211102_P01_WALL-PANEL-FRAME-SIDE-LOWER-RH_CAD (Autodesk Fusion 360 design; units mm, degrees)
description: WALL - PANEL FRAME - SIDE LOWER - RH | Vách phải - khung dưới | P01 | position R1
part number: 211102
description: WALL - PANEL FRAME - SIDE LOWER - RH | Vách phải - khung dưới | P01
Autodesk Fusion 360 part; units mm, degrees
ref_plane "WorkPlane1" through (0, 0, 112.26) normal (0, 0, 1) x (1, 0, 0) in component "211102 WALL - PANEL FRAME - SIDE LOWER - RH"
sketch "SKETCH - RAIL - BOTTOM TUBE" plane through (0, 0, 112.26) normal (0, 0, 1) x (1, 0, 0) in component "211102 WALL - PANEL FRAME - SIDE LOWER - RH"
  line L0 (1204, -642.74) -> (1244, -642.74)
  line L1 (1244, -642.74) -> (1244, 847)
  line L2 (1244, 847) -> (1204, 847)
  line L3 (1204, 847) -> (1204, -642.74)
  dimension "d494" = 40
  dimension "d495" = 1489.74
  dimension "d496" = 1204
  dimension "d497" = 642.74
  constraint horizontal L0
  constraint vertical L1
  constraint horizontal L2
  constraint vertical L3
  measures "d494" horizontal distance of L0.start L0.end
  measures "d495" vertical distance of L0.start L2.end
  measures "d496" horizontal distance of origin L0.start
  measures "d497" vertical distance of origin L0.start
extrude "EXTRUDE - RAIL - BOTTOM TUBE" add sketch "SKETCH - RAIL - BOTTOM TUBE" along normal blind 20 makes body 1 in component "211102 WALL - PANEL FRAME - SIDE LOWER - RH"
ref_plane "WorkPlane2" through (0, 0, 113.46) normal (0, 0, 1) x (1, 0, 0) in component "211102 WALL - PANEL FRAME - SIDE LOWER - RH"
sketch "SKETCH - RAIL - BOTTOM BORE" plane through (0, 0, 113.46) normal (0, 0, 1) x (1, 0, 0) in component "211102 WALL - PANEL FRAME - SIDE LOWER - RH"
  line L0 (1205.2, -642.74) -> (1242.8, -642.74)
  line L1 (1242.8, -642.74) -> (1242.8, 847)
  line L2 (1242.8, 847) -> (1205.2, 847)
  line L3 (1205.2, 847) -> (1205.2, -642.74)
  dimension "d502" = 37.6
  dimension "d503" = 1489.74
  dimension "d504" = 1205.2
  dimension "d505" = 642.74
  constraint horizontal L0
  constraint vertical L1
  constraint horizontal L2
  constraint vertical L3
  measures "d502" horizontal distance of L0.start L0.end
  measures "d503" vertical distance of L0.start L2.end
  measures "d504" horizontal distance of origin L0.start
  measures "d505" vertical distance of origin L0.start
extrude "CUT - RAIL - BOTTOM BORE" cut sketch "SKETCH - RAIL - BOTTOM BORE" along normal blind 17.6 bodies 1 in component "211102 WALL - PANEL FRAME - SIDE LOWER - RH"
ref_plane "WorkPlane3" through (0, 0, 1235) normal (0, 0, 1) x (1, 0, 0) in component "211102 WALL - PANEL FRAME - SIDE LOWER - RH"
sketch "SKETCH - RAIL - TOP TUBE" plane through (0, 0, 1235) normal (0, 0, 1) x (1, 0, 0) in component "211102 WALL - PANEL FRAME - SIDE LOWER - RH"
  line L0 (1204, -642.74) -> (1244, -642.74)
  line L1 (1244, -642.74) -> (1244, 847)
  line L2 (1244, 847) -> (1204, 847)
  line L3 (1204, 847) -> (1204, -642.74)
  dimension "d510" = 40
  dimension "d511" = 1489.74
  dimension "d512" = 1204
  dimension "d513" = 642.74
  constraint horizontal L0
  constraint vertical L1
  constraint horizontal L2
  constraint vertical L3
  measures "d510" horizontal distance of L0.start L0.end
  measures "d511" vertical distance of L0.start L2.end
  measures "d512" horizontal distance of origin L0.start
  measures "d513" vertical distance of origin L0.start
extrude "EXTRUDE - RAIL - TOP TUBE" add sketch "SKETCH - RAIL - TOP TUBE" along normal blind 20 separate body makes body 2 in component "211102 WALL - PANEL FRAME - SIDE LOWER - RH"
ref_plane "WorkPlane4" through (0, 0, 1236.2) normal (0, 0, 1) x (1, 0, 0) in component "211102 WALL - PANEL FRAME - SIDE LOWER - RH"
sketch "SKETCH - RAIL - TOP BORE" plane through (0, 0, 1236.2) normal (0, 0, 1) x (1, 0, 0) in component "211102 WALL - PANEL FRAME - SIDE LOWER - RH"
  line L0 (1205.2, -642.74) -> (1242.8, -642.74)
  line L1 (1242.8, -642.74) -> (1242.8, 847)
  line L2 (1242.8, 847) -> (1205.2, 847)
  line L3 (1205.2, 847) -> (1205.2, -642.74)
  dimension "d518" = 37.6
  dimension "d519" = 1489.74
  dimension "d520" = 1205.2
  dimension "d521" = 642.74
  constraint horizontal L0
  constraint vertical L1
  constraint horizontal L2
  constraint vertical L3
  measures "d518" horizontal distance of L0.start L0.end
  measures "d519" vertical distance of L0.start L2.end
  measures "d520" horizontal distance of origin L0.start
  measures "d521" vertical distance of origin L0.start
extrude "CUT - RAIL - TOP BORE" cut sketch "SKETCH - RAIL - TOP BORE" along normal blind 17.6 bodies 2 in component "211102 WALL - PANEL FRAME - SIDE LOWER - RH"
ref_plane "WorkPlane5" through (0, 0, 132.26) normal (0, 0, 1) x (1, 0, 0) in component "211102 WALL - PANEL FRAME - SIDE LOWER - RH"
sketch "SKETCH - STILE - FRONT TUBE" plane through (0, 0, 132.26) normal (0, 0, 1) x (1, 0, 0) in component "211102 WALL - PANEL FRAME - SIDE LOWER - RH"
  line L0 (1204, -642.74) -> (1244, -642.74)
  line L1 (1244, -642.74) -> (1244, -622.74)
  line L2 (1244, -622.74) -> (1204, -622.74)
  line L3 (1204, -622.74) -> (1204, -642.74)
  dimension "d526" = 40
  dimension "d527" = 20
  dimension "d528" = 1204
  dimension "d529" = 642.74
  constraint horizontal L0
  constraint vertical L1
  constraint horizontal L2
  constraint vertical L3
  measures "d526" horizontal distance of L0.start L0.end
  measures "d527" vertical distance of L0.start L2.end
  measures "d528" horizontal distance of origin L0.start
  measures "d529" vertical distance of origin L0.start
extrude "EXTRUDE - STILE - FRONT TUBE" add sketch "SKETCH - STILE - FRONT TUBE" along normal blind 1102.74 separate body makes body 3 in component "211102 WALL - PANEL FRAME - SIDE LOWER - RH"
ref_plane "WorkPlane6" through (0, 0, 132.26) normal (0, 0, 1) x (1, 0, 0) in component "211102 WALL - PANEL FRAME - SIDE LOWER - RH"
sketch "SKETCH - STILE - FRONT BORE" plane through (0, 0, 132.26) normal (0, 0, 1) x (1, 0, 0) in component "211102 WALL - PANEL FRAME - SIDE LOWER - RH"
  line L0 (1205.2, -641.54) -> (1242.8, -641.54)
  line L1 (1242.8, -641.54) -> (1242.8, -623.94)
  line L2 (1242.8, -623.94) -> (1205.2, -623.94)
  line L3 (1205.2, -623.94) -> (1205.2, -641.54)
  dimension "d534" = 37.6
  dimension "d535" = 17.6
  dimension "d536" = 1205.2
  dimension "d537" = 641.54
  constraint horizontal L0
  constraint vertical L1
  constraint horizontal L2
  constraint vertical L3
  measures "d534" horizontal distance of L0.start L0.end
  measures "d535" vertical distance of L0.start L2.end
  measures "d536" horizontal distance of origin L0.start
  measures "d537" vertical distance of origin L0.start
extrude "CUT - STILE - FRONT BORE" cut sketch "SKETCH - STILE - FRONT BORE" along normal blind 1102.74 bodies 3 in component "211102 WALL - PANEL FRAME - SIDE LOWER - RH"
ref_plane "WorkPlane7" through (0, 0, 132.26) normal (0, 0, 1) x (1, 0, 0) in component "211102 WALL - PANEL FRAME - SIDE LOWER - RH"
sketch "SKETCH - STILE - BACK TUBE" plane through (0, 0, 132.26) normal (0, 0, 1) x (1, 0, 0) in component "211102 WALL - PANEL FRAME - SIDE LOWER - RH"
  line L0 (1204, 807) -> (1244, 807)
  line L1 (1244, 807) -> (1244, 847)
  line L2 (1244, 847) -> (1204, 847)
  line L3 (1204, 847) -> (1204, 807)
  dimension "d542" = 40
  dimension "d543" = 40
  dimension "d544" = 1204
  dimension "d545" = 807
  constraint horizontal L0
  constraint vertical L1
  constraint horizontal L2
  constraint vertical L3
  measures "d542" horizontal distance of L0.start L0.end
  measures "d543" vertical distance of L0.start L2.end
  measures "d544" horizontal distance of origin L0.start
  measures "d545" vertical distance of origin L0.start
extrude "EXTRUDE - STILE - BACK TUBE" add sketch "SKETCH - STILE - BACK TUBE" along normal blind 1102.74 separate body makes body 4 in component "211102 WALL - PANEL FRAME - SIDE LOWER - RH"
ref_plane "WorkPlane8" through (0, 0, 132.26) normal (0, 0, 1) x (1, 0, 0) in component "211102 WALL - PANEL FRAME - SIDE LOWER - RH"
sketch "SKETCH - STILE - BACK BORE" plane through (0, 0, 132.26) normal (0, 0, 1) x (1, 0, 0) in component "211102 WALL - PANEL FRAME - SIDE LOWER - RH"
  line L0 (1205.2, 808.2) -> (1242.8, 808.2)
  line L1 (1242.8, 808.2) -> (1242.8, 845.8)
  line L2 (1242.8, 845.8) -> (1205.2, 845.8)
  line L3 (1205.2, 845.8) -> (1205.2, 808.2)
  dimension "d550" = 37.6
  dimension "d551" = 37.6
  dimension "d552" = 1205.2
  dimension "d553" = 808.2
  constraint horizontal L0
  constraint vertical L1
  constraint horizontal L2
  constraint vertical L3
  measures "d550" horizontal distance of L0.start L0.end
  measures "d551" vertical distance of L0.start L2.end
  measures "d552" horizontal distance of origin L0.start
  measures "d553" vertical distance of origin L0.start
extrude "CUT - STILE - BACK BORE" cut sketch "SKETCH - STILE - BACK BORE" along normal blind 1102.74 bodies 4 in component "211102 WALL - PANEL FRAME - SIDE LOWER - RH"
ref_plane "WorkPlane9" through (0, 0, 132.26) normal (0, 0, 1) x (1, 0, 0) in component "211102 WALL - PANEL FRAME - SIDE LOWER - RH"
sketch "SKETCH - STILE - MID 1 TUBE" plane through (0, 0, 132.26) normal (0, 0, 1) x (1, 0, 0) in component "211102 WALL - PANEL FRAME - SIDE LOWER - RH"
  line L0 (1204, -277.805) -> (1244, -277.805)
  line L1 (1244, -277.805) -> (1244, -257.805)
  line L2 (1244, -257.805) -> (1204, -257.805)
  line L3 (1204, -257.805) -> (1204, -277.805)
  dimension "d558" = 40
  dimension "d559" = 20
  dimension "d560" = 1204
  dimension "d561" = 277.805
  constraint horizontal L0
  constraint vertical L1
  constraint horizontal L2
  constraint vertical L3
  measures "d558" horizontal distance of L0.start L0.end
  measures "d559" vertical distance of L0.start L2.end
  measures "d560" horizontal distance of origin L0.start
  measures "d561" vertical distance of origin L0.start
extrude "EXTRUDE - STILE - MID 1 TUBE" add sketch "SKETCH - STILE - MID 1 TUBE" along normal blind 1102.74 separate body makes body 5 in component "211102 WALL - PANEL FRAME - SIDE LOWER - RH"
ref_plane "WorkPlane10" through (0, 0, 132.26) normal (0, 0, 1) x (1, 0, 0) in component "211102 WALL - PANEL FRAME - SIDE LOWER - RH"
sketch "SKETCH - STILE - MID 1 BORE" plane through (0, 0, 132.26) normal (0, 0, 1) x (1, 0, 0) in component "211102 WALL - PANEL FRAME - SIDE LOWER - RH"
  line L0 (1205, -276.805) -> (1243, -276.805)
  line L1 (1243, -276.805) -> (1243, -258.805)
  line L2 (1243, -258.805) -> (1205, -258.805)
  line L3 (1205, -258.805) -> (1205, -276.805)
  dimension "d566" = 38
  dimension "d567" = 18
  dimension "d568" = 1205
  dimension "d569" = 276.805
  constraint horizontal L0
  constraint vertical L1
  constraint horizontal L2
  constraint vertical L3
  measures "d566" horizontal distance of L0.start L0.end
  measures "d567" vertical distance of L0.start L2.end
  measures "d568" horizontal distance of origin L0.start
  measures "d569" vertical distance of origin L0.start
extrude "CUT - STILE - MID 1 BORE" cut sketch "SKETCH - STILE - MID 1 BORE" along normal blind 1102.74 bodies 5 in component "211102 WALL - PANEL FRAME - SIDE LOWER - RH"
pattern_linear "PATTERN - STILES - MID" count 3 spacing 364.935 along (0, 1, 0) of bodies 5 makes body 6 at (1230.6667, 107.13, 499.84) makes body 7 at (1230.6667, 472.065, 499.84) in component "211102 WALL - PANEL FRAME - SIDE LOWER - RH"
ref_plane "WorkPlane11" through (0, 0, 112.26) normal (0, 0, 1) x (1, 0, 0) in component "211102 WALL - PANEL FRAME - SIDE LOWER - RH"
sketch "HOLE CENTRE - BOTTOM RAIL BOLT CLEARANCE 1" plane through (0, 0, 112.26) normal (0, 0, 1) x (1, 0, 0) in component "211102 WALL - PANEL FRAME - SIDE LOWER - RH"
  point P0 (1224, -422.74)
  dimension "d578" = 1224
  dimension "d579" = 422.74
  measures "d578" horizontal distance of origin P0
  measures "d579" vertical distance of origin P0
hole "HOLE - BOTTOM RAIL BOLT CLEARANCE 1" at (1224, -422.74, 112.26) direction (0, 0, 1) diameter 7 depth 1.2 tip angle 118 bodies 1 in component "211102 WALL - PANEL FRAME - SIDE LOWER - RH"
ref_plane "WorkPlane12" through (0, 0, 132.26) normal (0, 0, 1) x (1, 0, 0) in component "211102 WALL - PANEL FRAME - SIDE LOWER - RH"
sketch "HOLE CENTRE - BOTTOM RAIL KEY ACCESS 1" plane through (0, 0, 132.26) normal (0, 0, 1) x (1, 0, 0) in component "211102 WALL - PANEL FRAME - SIDE LOWER - RH"
  point P0 (1224, -422.74)
  dimension "d585" = 1224
  dimension "d586" = 422.74
  measures "d585" horizontal distance of origin P0
  measures "d586" vertical distance of origin P0
hole "HOLE - BOTTOM RAIL KEY ACCESS 1" at (1224, -422.74, 132.26) direction (0, 0, -1) diameter 19 depth 1.2 tip angle 118 bodies 1 in component "211102 WALL - PANEL FRAME - SIDE LOWER - RH"
pattern_linear "PATTERN - BOTTOM RAIL BOLT HOLES" count 4 spacing 350.9133 along (0, 1, 0) of "HOLE - BOTTOM RAIL BOLT CLEARANCE 1", "HOLE - BOTTOM RAIL KEY ACCESS 1" in component "211102 WALL - PANEL FRAME - SIDE LOWER - RH"
ref_plane "WorkPlane13" through (0, 0, 112.26) normal (0, 0, 1) x (1, 0, 0) in component "211102 WALL - PANEL FRAME - SIDE LOWER - RH"
sketch "HOLE CENTRE - BOTTOM RAIL SPIGOT ROUND" plane through (0, 0, 112.26) normal (0, 0, 1) x (1, 0, 0) in component "211102 WALL - PANEL FRAME - SIDE LOWER - RH"
  point P0 (1224, -542.74)
  dimension "d596" = 1224
  dimension "d597" = 542.74
  measures "d596" horizontal distance of origin P0
  measures "d597" vertical distance of origin P0
hole "HOLE - BOTTOM RAIL SPIGOT ROUND" at (1224, -542.74, 112.26) direction (0, 0, 1) diameter 8.5 depth 1.2 tip angle 118 bodies 1 in component "211102 WALL - PANEL FRAME - SIDE LOWER - RH"
ref_plane "WorkPlane14" through (0, 0, 112.26) normal (0, 0, 1) x (1, 0, 0) in component "211102 WALL - PANEL FRAME - SIDE LOWER - RH"
sketch "SKETCH - BOTTOM RAIL SPIGOT SLOT" plane through (0, 0, 112.26) normal (0, 0, 1) x (1, 0, 0) in component "211102 WALL - PANEL FRAME - SIDE LOWER - RH"
  line L0 (1221.25, 745.75) -> (1226.75, 745.75)
  line L1 (1226.75, 745.75) -> (1226.75, 754.25)
  line L2 (1226.75, 754.25) -> (1221.25, 754.25)
  line L3 (1221.25, 754.25) -> (1221.25, 745.75)
  dimension "d603" = 5.5
  dimension "d604" = 8.5
  dimension "d605" = 1221.25
  dimension "d606" = 745.75
  constraint horizontal L0
  constraint vertical L1
  constraint horizontal L2
  constraint vertical L3
  measures "d603" horizontal distance of L0.start L0.end
  measures "d604" vertical distance of L0.start L2.end
  measures "d605" horizontal distance of origin L0.start
  measures "d606" vertical distance of origin L0.start
extrude "CUT - BOTTOM RAIL SPIGOT SLOT" cut sketch "SKETCH - BOTTOM RAIL SPIGOT SLOT" along normal blind 1.2 bodies 1 in component "211102 WALL - PANEL FRAME - SIDE LOWER - RH"
ref_plane "WorkPlane15" through (0, 0, 112.26) normal (0, 0, 1) x (1, 0, 0) in component "211102 WALL - PANEL FRAME - SIDE LOWER - RH"
sketch "HOLE CENTRE - BOTTOM RAIL SPIGOT SLOT END 1" plane through (0, 0, 112.26) normal (0, 0, 1) x (1, 0, 0) in component "211102 WALL - PANEL FRAME - SIDE LOWER - RH"
  point P0 (1221.25, 750)
  dimension "d611" = 1221.25
  dimension "d612" = 750
  measures "d611" horizontal distance of origin P0
  measures "d612" vertical distance of origin P0
hole "HOLE - BOTTOM RAIL SPIGOT SLOT END 1" at (1221.25, 750, 112.26) direction (0, 0, 1) diameter 8.5 depth 1.2 tip angle 118 bodies 1 in component "211102 WALL - PANEL FRAME - SIDE LOWER - RH"
ref_plane "WorkPlane16" through (0, 0, 112.26) normal (0, 0, 1) x (1, 0, 0) in component "211102 WALL - PANEL FRAME - SIDE LOWER - RH"
sketch "HOLE CENTRE - BOTTOM RAIL SPIGOT SLOT END 2" plane through (0, 0, 112.26) normal (0, 0, 1) x (1, 0, 0) in component "211102 WALL - PANEL FRAME - SIDE LOWER - RH"
  point P0 (1226.75, 750)
  dimension "d618" = 1226.75
  dimension "d619" = 750
  measures "d618" horizontal distance of origin P0
  measures "d619" vertical distance of origin P0
hole "HOLE - BOTTOM RAIL SPIGOT SLOT END 2" at (1226.75, 750, 112.26) direction (0, 0, 1) diameter 8.5 depth 1.2 tip angle 118 bodies 1 in component "211102 WALL - PANEL FRAME - SIDE LOWER - RH"
ref_plane "WorkPlane17" through (0, 0, 1255) normal (0, 0, 1) x (1, 0, 0) in component "211102 WALL - PANEL FRAME - SIDE LOWER - RH"
sketch "HOLE CENTRE - TOP RAIL RIVNUT 1" plane through (0, 0, 1255) normal (0, 0, 1) x (1, 0, 0) in component "211102 WALL - PANEL FRAME - SIDE LOWER - RH"
  point P0 (1224, -422.74)
  dimension "d625" = 1224
  dimension "d626" = 422.74
  measures "d625" horizontal distance of origin P0
  measures "d626" vertical distance of origin P0
hole "HOLE - TOP RAIL RIVNUT 1" at (1224, -422.74, 1255) direction (0, 0, -1) diameter 9.53 depth 1.2 tip angle 118 bodies 2 in component "211102 WALL - PANEL FRAME - SIDE LOWER - RH"
pattern_linear "PATTERN - TOP RAIL RIVNUTS" count 4 spacing 350.9133 along (0, 1, 0) of "HOLE - TOP RAIL RIVNUT 1" in component "211102 WALL - PANEL FRAME - SIDE LOWER - RH"
ref_plane "WorkPlane18" through (0, 0, 1255) normal (0, 0, 1) x (1, 0, 0) in component "211102 WALL - PANEL FRAME - SIDE LOWER - RH"
sketch "HOLE CENTRE - TOP RAIL SPIGOT RIVNUT FRONT" plane through (0, 0, 1255) normal (0, 0, 1) x (1, 0, 0) in component "211102 WALL - PANEL FRAME - SIDE LOWER - RH"
  point P0 (1224, -542.74)
  dimension "d636" = 1224
  dimension "d637" = 542.74
  measures "d636" horizontal distance of origin P0
  measures "d637" vertical distance of origin P0
hole "HOLE - TOP RAIL SPIGOT RIVNUT FRONT" at (1224, -542.74, 1255) direction (0, 0, -1) diameter 9.53 depth 1.2 tip angle 118 bodies 2 in component "211102 WALL - PANEL FRAME - SIDE LOWER - RH"
ref_plane "WorkPlane19" through (0, 0, 1255) normal (0, 0, 1) x (1, 0, 0) in component "211102 WALL - PANEL FRAME - SIDE LOWER - RH"
sketch "HOLE CENTRE - TOP RAIL SPIGOT RIVNUT BACK" plane through (0, 0, 1255) normal (0, 0, 1) x (1, 0, 0) in component "211102 WALL - PANEL FRAME - SIDE LOWER - RH"
  point P0 (1224, 750)
  dimension "d643" = 1224
  dimension "d644" = 750
  measures "d643" horizontal distance of origin P0
  measures "d644" vertical distance of origin P0
hole "HOLE - TOP RAIL SPIGOT RIVNUT BACK" at (1224, 750, 1255) direction (0, 0, -1) diameter 9.53 depth 1.2 tip angle 118 bodies 2 in component "211102 WALL - PANEL FRAME - SIDE LOWER - RH"
ref_plane "WorkPlane20" through (0, -642.74, 0) normal (0, 1, 0) x (0, 0, 1) in component "211102 WALL - PANEL FRAME - SIDE LOWER - RH"
sketch "HOLE CENTRE - FRONT STILE BOLT CLEARANCE 1" plane through (0, -642.74, 0) normal (0, 1, 0) x (1, 0, 0) in component "211102 WALL - PANEL FRAME - SIDE LOWER - RH"
  point P0 (1224, -332.26)
  dimension "d650" = 1224
  dimension "d651" = 332.26
  measures "d650" horizontal distance of origin P0
  measures "d651" vertical distance of origin P0
hole "HOLE - FRONT STILE BOLT CLEARANCE 1" at (1224, -642.74, 332.26) direction (0, 1, 0) diameter 7 depth 1.2 tip angle 118 bodies 3 in component "211102 WALL - PANEL FRAME - SIDE LOWER - RH"
ref_plane "WorkPlane21" through (0, -622.74, 0) normal (0, 1, 0) x (0, 0, 1) in component "211102 WALL - PANEL FRAME - SIDE LOWER - RH"
sketch "HOLE CENTRE - FRONT STILE KEY ACCESS 1" plane through (0, -622.74, 0) normal (0, 1, 0) x (1, 0, 0) in component "211102 WALL - PANEL FRAME - SIDE LOWER - RH"
  point P0 (1224, -332.26)
  dimension "d657" = 1224
  dimension "d658" = 332.26
  measures "d657" horizontal distance of origin P0
  measures "d658" vertical distance of origin P0
hole "HOLE - FRONT STILE KEY ACCESS 1" at (1224, -622.74, 332.26) direction (0, -1, 0) diameter 19 depth 1.2 tip angle 118 bodies 3 in component "211102 WALL - PANEL FRAME - SIDE LOWER - RH"
pattern_linear "PATTERN - FRONT STILE BOLT HOLES" count 3 spacing 351.37 along (0, 0, 1) of "HOLE - FRONT STILE BOLT CLEARANCE 1", "HOLE - FRONT STILE KEY ACCESS 1" in component "211102 WALL - PANEL FRAME - SIDE LOWER - RH"
ref_plane "WorkPlane22" through (1204, 0, 0) normal (1, 0, 0) x (0, 1, 0) in component "211102 WALL - PANEL FRAME - SIDE LOWER - RH"
sketch "HOLE CENTRE - BACK STILE CORNER RIVNUT 1" plane through (1204, 0, 0) normal (1, 0, 0) x (0, 0, -1) in component "211102 WALL - PANEL FRAME - SIDE LOWER - RH"
  point P0 (-332.26, 824)
  dimension "d668" = 824
  dimension "d669" = 332.26
  measures "d668" vertical distance of origin P0
  measures "d669" horizontal distance of origin P0
hole "HOLE - BACK STILE CORNER RIVNUT 1" at (1204, 824, 332.26) direction (1, 0, 0) diameter 9.53 depth 1.2 tip angle 118 bodies 4 in component "211102 WALL - PANEL FRAME - SIDE LOWER - RH"
pattern_linear "PATTERN - BACK STILE CORNER RIVNUTS" count 3 spacing 339.305 along (0, 0, 1) of "HOLE - BACK STILE CORNER RIVNUT 1" in component "211102 WALL - PANEL FRAME - SIDE LOWER - RH"
component "211102 WALL - PANEL FRAME - SIDE LOWER - RH" placed x (1, 0, 0) y (0, 1, 0) z (0, 0, 1) at (0, 0, 0)
equation "pod_w_Ref = 2500 mm" comment "DECIDED: D-01; conventions s4 (X = +-1250)"
equation "pod_d_Ref = 1700 mm" comment "DECIDED: D-01; conventions s4 (Y = +-850)"
equation "pod_h_Ref = 2400 mm" comment "DECIDED: D-21 (room floor to roof skin top)"
equation "glide_h_Ref = 10 mm" comment "ASSUMPTION: layout study inputs.py glide_h"
equation "band_h_Ref = 100 mm" comment "SOURCE: layout study B1 list B-BAND 100x40; inputs.py base_h"
equation "outer_t_Ref = skin_t_Ref + bond_t_Ref + frame_t_Ref" comment "DECIDED: PM ruling 2026-10-31: ACP 3 + bond line 3 + frame 40, walls and ceiling (was 43)"
equation "cav_gap_Ref = 4 mm" comment "DECIDED: D-16, D-42: the gap between the outer panel and the lining cassette in the wall and ceiling stack"
equation "cass_t_Ref = 34 mm" comment "SOURCE: layout study B1 final list L-CASS 34 (tray + 25 gap + felt 9)"
equation "stack_t_Ref = outer_t_Ref + cav_gap_Ref + cass_t_Ref" comment "CALCULATION: D-16, D-42 stack, walls and ceiling: outer panel + cavity gap + cassette (PM ruling 2026-10-31 on outer_t)"
equation "wall_depth_Ref = 1495 mm" comment "DECIDED: PM ruling pass C: side walls start at the decor back plate (Y -645), as v1 (1496)"
equation "lin_gap_Ref = 4 mm" comment "ASSUMPTION: PM ruling pass C: gap above the upper side linings so they stay floating (= the 4 mm stack gap)"
equation "seam_gap_Ref = 2.26 mm" comment "DECIDED: PM ruling 2026-10-31 (Mechanical Checker F-001, F-005): the Joints Engineer's 2.26 mm at all nine site seam types, set by a metal stop (1.5 stop washer + 0.76 rivnut head; joints register section 2.8)"
equation "wall_z0_Ref = glide_h_Ref + band_h_Ref" comment "CALCULATION: base band top: glides + band"
equation "panel_z0_Ref = wall_z0_Ref + seam_gap_Ref" comment "CALCULATION: walls stand one seam_gap above the band top (joints register 2.8, IF-01)"
equation "wall_h_Ref = pod_h_Ref - wall_z0_Ref" comment "CALCULATION: 2290 = layout study v2_model wall_h"
equation "side_h_Ref = ( wall_h_Ref - 2 * seam_gap_Ref ) / 2" comment "CALCULATION: D-23: 2 sheets per side wall; the gap on the band and the horizontal seam (joints register 2.8)"
equation "back_oh_Ref = pod_h_Ref - outer_t_Ref - seam_gap_Ref - panel_z0_Ref" comment "CALCULATION: PM ruling 2026-10-31 (pass D, F-004): the back outer frames run up to the ceiling frame (pod_h - outer_t), less the seam_gap under it, closing the slot at the back top edge"
equation "back_ph_Ref = ( back_oh_Ref - seam_gap_Ref ) / 2" comment "CALCULATION: D-23: 4 sheets on the back, two equal rows with one seam_gap between them (joints register 2.8); the lower back linings match the lower row, as on the side walls"
equation "skin_t_Ref = 3 mm" comment "DECIDED: ACP skin, walls and ceiling (D-16; PM ruling 2026-10-31 on outer_t)"
equation "bond_t_Ref = 3 mm" comment "DECIDED: bond line between the ACP and the frame (PM ruling 2026-10-31 on outer_t)"
equation "frame_t_Ref = 40 mm" comment "DECIDED: aluminium frame tube depth, walls and ceiling (PM ruling 2026-10-31 on outer_t)"
equation "pod_h_Ref1 = 2400 mm" comment "DECIDED: D-21 (room floor to roof skin top)"
equation "outer_t_Ref1 = skin_t_Ref1 + bond_t_Ref1 + frame_t_Ref1" comment "DECIDED: PM ruling 2026-10-31: ACP 3 + bond line 3 + frame 40, walls and ceiling (was 43)"
equation "n_base_bolt_Ref = 4" comment "DECIDED: PM ruling 2026-10-31, J-BASE-01: bolts per panel along the band, evenly spaced"
equation "skin_t_Ref1 = 3 mm" comment "DECIDED: ACP skin, walls and ceiling (D-16; PM ruling 2026-10-31 on outer_t)"
equation "bond_t_Ref1 = 3 mm" comment "DECIDED: bond line between the ACP and the frame (PM ruling 2026-10-31 on outer_t)"
equation "frame_t_Ref1 = 40 mm" comment "DECIDED: aluminium frame tube depth, walls and ceiling (PM ruling 2026-10-31 on outer_t)"
equation "bolt_edge_inset_Ref = 220 mm" comment "DECIDED: PM ruling 2026-10-31: on every bolted edge the end bolts sit this far in from each panel end (the FRAME end, where the bolts go), the rest evenly spaced"
equation "spigot_inset_Ref = 100 mm" comment "DECIDED: PM ruling 2026-10-31: locating spigots this far in from each panel end (round hole at one end, slot at the other)"
equation "ceil_bolt_z_Ref = pod_h_Ref1 - outer_t_Ref1 + frame_t_Ref1 / 2" comment "DECIDED: PM ruling 2026-10-31, J-CEIL-01 wall to ceiling: the bolt line on the ceiling frame's centre (Z 2374)"
equation "pod_w = pod_w_Ref" comment "LINKED: pod_w_Ref, derived from 100000_P04_POD-SKELETON_CAD v4 (skeleton is the single source)"
equation "pod_d = pod_d_Ref" comment "LINKED: pod_d_Ref, derived from 100000_P04_POD-SKELETON_CAD v4 (skeleton is the single source)"
equation "pod_h = pod_h_Ref" comment "LINKED: pod_h_Ref, derived from 100000_P04_POD-SKELETON_CAD v4 (skeleton is the single source)"
equation "wall_depth = wall_depth_Ref" comment "LINKED: wall_depth_Ref, derived from 100000_P04_POD-SKELETON_CAD v4 (skeleton is the single source)"
equation "wall_z0 = wall_z0_Ref" comment "LINKED: wall_z0_Ref, derived from 100000_P04_POD-SKELETON_CAD v4 (skeleton is the single source)"
equation "panel_z0 = panel_z0_Ref" comment "LINKED: panel_z0_Ref, derived from 100000_P04_POD-SKELETON_CAD v4 (skeleton is the single source)"
equation "side_h = side_h_Ref" comment "LINKED: side_h_Ref, derived from 100000_P04_POD-SKELETON_CAD v4 (skeleton is the single source)"
equation "back_ph = back_ph_Ref" comment "LINKED: back_ph_Ref, derived from 100000_P04_POD-SKELETON_CAD v4 (skeleton is the single source)"
equation "stack_t = stack_t_Ref" comment "LINKED: stack_t_Ref, derived from 100000_P04_POD-SKELETON_CAD v4 (skeleton is the single source)"
equation "outer_t = outer_t_Ref" comment "LINKED: outer_t_Ref, derived from 100000_P04_POD-SKELETON_CAD v4 (skeleton is the single source)"
equation "cass_t = cass_t_Ref" comment "LINKED: cass_t_Ref, derived from 100000_P04_POD-SKELETON_CAD v4 (skeleton is the single source)"
equation "lin_gap = lin_gap_Ref" comment "LINKED: lin_gap_Ref, derived from 100000_P04_POD-SKELETON_CAD v4 (skeleton is the single source)"
equation "seam_gap = seam_gap_Ref" comment "LINKED: seam_gap_Ref, derived from 100000_P04_POD-SKELETON_CAD v4 (skeleton is the single source)"
equation "skin_t = skin_t_Ref" comment "LINKED: skin_t_Ref, derived from 100000_P04_POD-SKELETON_CAD v4 (skeleton is the single source)"
equation "bond_t = bond_t_Ref" comment "LINKED: bond_t_Ref, derived from 100000_P04_POD-SKELETON_CAD v4 (skeleton is the single source)"
equation "bolt_edge_inset = bolt_edge_inset_Ref" comment "LINKED: bolt_edge_inset_Ref, derived from 100000_P04_POD-SKELETON_CAD v4 (skeleton is the single source)"
equation "spigot_inset = spigot_inset_Ref" comment "LINKED: spigot_inset_Ref, derived from 100000_P04_POD-SKELETON_CAD v4 (skeleton is the single source)"
equation "n_base_bolt = n_base_bolt_Ref" comment "LINKED: n_base_bolt_Ref, derived from 100000_P04_POD-SKELETON_CAD v4 (skeleton is the single source)"
equation "ceil_bolt_z = ceil_bolt_z_Ref" comment "LINKED: ceil_bolt_z_Ref, derived from 100000_P04_POD-SKELETON_CAD v4 (skeleton is the single source)"
equation "tube_w = 20 mm" comment "CONFIRMED: D-34, D-54: aluminium tube 20 x 40 x 1.2; the 20 mm face carries the skin, so the 40 mm runs through the wall (outer_t = ACP 3 + frame 40). The joint register may turn it for the bond width (HOLD)"
equation "tube_d = outer_t - skin_t - bond_t" comment "CALCULATION: frame depth = outer panel 46 - skin 3 - bond 3 = 40 (D-34)"
equation "tube_t = 1.2 mm" comment "CONFIRMED: D-34, D-54, D-85: perimeter members (rails, front and back stiles) keep the 1.2 mm wall; they carry the rivnuts (grip check passed)"
equation "stud_t = 1.0 mm" comment "CONFIRMED: D-85 (weight): intermediate studs at a 1.0 mm wall; they carry no rivnut, only the skin's bond line"
equation "stile_pitch_max = 400 mm" comment "CONFIRMED: D-16, D-34: members 400 mm apart or less, to keep the ACP flat"
equation "pnl_len = wall_depth - seam_gap" comment "CALCULATION: D-49 depth 1495 less the 2.26 gap at the decor back plate (PM ruling on F-008): 1492.74"
equation "pnl_h = side_h" comment "CALCULATION: skeleton side_h: 2 sheets per side wall (D-23) with the seam gaps"
equation "skin_ret = outer_t - skin_t" comment "ASSUMPTION: back return of the side skin: covers the frame's back end at the corner, where the side skin covers the back panel's edge (D-55; sample drawing D04). V-groove and fold per the ACP maker (HOLD H16)"
equation "skin_setback = 0 mm" comment "ASSUMPTION: skin edge set back from the frame's top and bottom edges: 0, so the outside reveal equals the 2.26 seam gap (D-23: crisp, aligned reveals; joints register 2.8 leaves the setback to the WALL drawing)"
equation "frm_len = pnl_len - skin_t" comment "CALCULATION: the frame stops at the inside of the skin's back return"
equation "frm_h = pnl_h" comment "ASSUMPTION: the frame fills the skeleton envelope height; seam and base gasket gaps are set by the joint register (HOLD)"
equation "corner_w = 40 mm" comment "CONFIRMED: the side panel's back member is 40 x 40 x 1.2 (PM ruling on the joints register, item 3, 2026-10-31; register F2, FR-06): the back corner joint needs a 37+ mm overlap for the rivnut and the bolt"
equation "stile_n_mid = ceil(( frm_len - tube_w / 2 - corner_w / 2 ) / stile_pitch_max) - 1" comment "CALCULATION: intermediate stiles so that no stile pitch (centre to centre) exceeds stile_pitch_max"
equation "stile_pitch = ( frm_len - tube_w / 2 - corner_w / 2 ) / ( stile_n_mid + 1 )" comment "CALCULATION: equal stile pitch, centre to centre, from the front stile to the 40 mm back stile"
equation "top_h = tube_w" comment "CALCULATION: top member height: 20 on a lower panel; 40 x 40 on an upper panel, where the ceiling bolts in (PM ruling R-J3, joints register FR-06)"
equation "stile_len = frm_h - tube_w - top_h" comment "CALCULATION: stiles fit between the full-length rails (butt joints)"
equation "ceil_bolt_dz = pod_h - ceil_bolt_z" comment "CALCULATION: J-CEIL-01 side bolts on the ceiling frame tube's centre: the skeleton's ceil_bolt_z, Z 2374 on P04 (joints register R-J15, FR-07)"
equation "fill_t = tube_d" comment "CALCULATION: 40 mm PET fill fills the frame depth (D-34; layout study 40 mm)"
equation "bolt_d = 7 mm" comment "CONFIRMED: PM ruling on F-009: bolt holes 7.0 (0.51 float), position tolerance 0.4 (+-0.2) from the spigot hole, CNC or drill jig (joints register FR-02)"
equation "access_d = 19 mm" comment "CALCULATION: register FR-03: passes the 18 mm head washer (ISO 7093-1, R-J10), the M6 head and the 5 mm key; holds the grommet retainer (H-02)"
equation "bolt_line_y = pod_d / 2 - skin_t - bond_t - tube_d / 2" comment "CONFIRMED: J-WALL-02 bolt line on the back panel's tube centre, Y 824 (joints register R-J15, FR-07)"
equation "rivnut_d = 9.53 mm" comment "SOURCE: Sherex CAH3-610-4.2 hole 9.53 +0.10 (HW-SEL A5; register H-03)"
equation "spigot_d = 8.5 mm" comment "ASSUMPTION: register FR-05: hole for the 8 mm locating spigot H-05"
equation "spigot_slot = 14 mm" comment "ASSUMPTION: register FR-05: slot length for the second spigot"
equation "spigot_edge = spigot_inset" comment "CALCULATION: the skeleton's spigot_inset: spigots 100 from each end of the edge (PM ruling 2026-10-31, R-J13)"
equation "bolt_edge = bolt_edge_inset" comment "CALCULATION: the skeleton's bolt_edge_inset: end bolts 220 in from the panel's ends, evenly spaced, every bolt 30 or more from any stile (PM ruling 2026-10-31, R-J14)"
equation "n_side_jnt = 3" comment "SOURCE: register J-WALL-02, J-FRONT-01: 3 bolts up each side panel"
equation "side_jnt_pitch = ( pnl_h - 2 * bolt_edge ) / ( n_side_jnt - 1 )" comment "CALCULATION: equal pitch of the 3 bolts up the corner and decor joints"
equation "pocket_w = 60 mm" comment "ASSUMPTION: register FR-10: fill left out 60 x 60 next to each bolt for the key"
equation "corner_z0 = panel_z0" comment "CALCULATION: bottom of the back panel row this side panel meets at the corner (B1/B2 or B3/B4, skeleton P04)"
equation "corner_bolt_pitch = ( back_ph - 2 * bolt_edge ) / ( n_side_jnt - 1 )" comment "CALCULATION: J-WALL-02 bolts run along the back panel's edge: 220, 559.31, 898.61 on its 1118.61 (joints register 2.9)"
equation "n_len_bolt = n_base_bolt" comment "CALCULATION: the skeleton's n_base_bolt (4): the same count on J-WALL-01 and the J-CEIL-01 side edges (register 2.9)"
equation "ceil_bolt_pitch = ( wall_depth - 2 * bolt_edge ) / ( n_len_bolt - 1 )" comment "CALCULATION: J-CEIL-01 side edge: 4 bolts along the ceiling's 1495 from Y -645 (its front edge), 220 rule, pitch 351.67 on P04; CEILING drills the same (PM ruling 2026-10-31 16:55; joints register 2.9)"
equation "len_bolt_pitch = ( pnl_len - 2 * bolt_edge ) / ( n_len_bolt - 1 )" comment "CALCULATION: even pitch of the bolts along the panel"
equation "felt_t = 9 mm" comment "SOURCE: plan VT03-PET 9 mm PET felt; HW-SEL A3; D-31 (the factory's felt)"
equation "tray_t = 0.5 mm" comment "CONFIRMED: D-37: galvanised steel tray 0.5 mm"
equation "tray_h = cass_t" comment "CONFIRMED: PM ruling 2026-10-31 (WALL group, option 1): the wall cassettes use the ceiling's tray, returns the full cassette depth (34) turned in as lips that hold the felt, no ribs; settles H09 for the walls"
equation "lip_w = 12 mm" comment "CONFIRMED: PM ruling 2026-10-31 (WALL group, option 1): 12 mm lips hold the felt edge"
equation "bend_r = tray_t" comment "ASSUMPTION: inside bend radius 1 x t for 0.5 mm DX51D (the sheet metal rule's bend radius is its Thickness); the factory's tooling sets it (guideline 9)"
equation "felt_c = 1 mm" comment "ASSUMPTION: felt edge clearance inside the returns, as the ceiling cassette"
equation "gap_h = tray_h - felt_t - 2 * tray_t" comment "CALCULATION: air gap between the tray base and the felt (24): the acoustic gap (D-17) and the cable path (D-26)"
equation "cass_len = wall_depth - stack_t + cass_t" comment "CALCULATION: = 1448: from the decor back plate to past the back cassette's face, closing the inside corner (D-57)"
equation "cass_h = side_h" comment "CALCULATION: lower: the panel height; upper: stops lin_gap under the roof frame so it floats (D-57)"
equation "clip_zone_h = 60 mm" comment "ASSUMPTION: height of each reserved clip zone (H03: no clip named)"
equation "clip_zone_dz = 100 mm" comment "ASSUMPTION: clip zone centre from the cassette's top and bottom edges (H03)"
equation "stopw_od = 20 mm" comment "SOURCE: joints register H-08: stop washer Ø10.5 x Ø20 x 1.5 (PROPOSED part)"
equation "stopw_id = 10.5 mm" comment "SOURCE: joints register H-08"
equation "stopw_t = 1.5 mm" comment "SOURCE: joints register H-08: rivnut head 0.76 + washer 1.5 = the 2.26 stop (R-J5)"
equation "rivnut_head_d = 12.96 mm" comment "SOURCE: Sherex CAH3-610-4.2 head Ø12.96 (joints register H-03, SHX)"
equation "rivnut_head_t = 0.76 mm" comment "SOURCE: Sherex CAH3-610-4.2 head 0.76 ±0.08 (H-03, SHX)"
equation "rivnut_body_d = 9.5 mm" comment "SOURCE: Sherex CAH3-610-4.2 body Ø9.50 max (H-03, SHX)"
equation "rivnut_len = 10.16 mm" comment "SOURCE: Sherex CAH3-610-4.2 installed length 10.16 max under the head (H-03, SHX); the bulge inside the tube is not modelled"
equation "m6_d = 6 mm" comment "CALCULATION: M6 threads shown at their 6 mm major diameter (no modelled thread)"
equation "spigot_pin_d = 8 mm" comment "SOURCE: joints register H-05: Ø8 stainless pin (PROPOSED, assumption sizes)"
equation "spigot_proud = 8 mm" comment "SOURCE: joints register H-05: stands 8 proud (read as: of the joint face)"
equation "spigot_thread_l = 10 mm" comment "ASSUMPTION: M6 thread into the spigot rivnut; H-05 gives no length; 10 stays inside the rivnut's 10.16"
equation "d492 = panel_z0"
equation "d494 = ( ( pod_w / 2 - skin_t - bond_t ) ) - ( ( pod_w / 2 - outer_t ) )"
equation "d495 = ( pod_d / 2 - skin_t ) - ( pod_d / 2 - wall_depth + seam_gap )"
equation "d496 = abs(( pod_w / 2 - outer_t ))"
equation "d497 = abs(pod_d / 2 - wall_depth + seam_gap)"
equation "d498 = ( ( panel_z0 ) + tube_w ) - ( panel_z0 )"
equation "d500 = ( panel_z0 ) + tube_t"
equation "d502 = ( ( ( pod_w / 2 - skin_t - bond_t ) ) - tube_t ) - ( ( ( pod_w / 2 - outer_t ) ) + tube_t )"
equation "d503 = ( pod_d / 2 - skin_t ) - ( pod_d / 2 - wall_depth + seam_gap )"
equation "d504 = abs(( ( pod_w / 2 - outer_t ) ) + tube_t)"
equation "d505 = abs(pod_d / 2 - wall_depth + seam_gap)"
equation "d506 = ( ( ( panel_z0 ) + tube_w ) - tube_t ) - ( ( panel_z0 ) + tube_t )"
equation "d508 = ( panel_z0 + side_h ) - top_h"
equation "d510 = ( ( pod_w / 2 - skin_t - bond_t ) ) - ( ( pod_w / 2 - outer_t ) )"
equation "d511 = ( pod_d / 2 - skin_t ) - ( pod_d / 2 - wall_depth + seam_gap )"
equation "d512 = abs(( pod_w / 2 - outer_t ))"
equation "d513 = abs(pod_d / 2 - wall_depth + seam_gap)"
equation "d514 = ( panel_z0 + side_h ) - ( ( panel_z0 + side_h ) - top_h )"
equation "d516 = ( ( panel_z0 + side_h ) - top_h ) + tube_t"
equation "d518 = ( ( ( pod_w / 2 - skin_t - bond_t ) ) - tube_t ) - ( ( ( pod_w / 2 - outer_t ) ) + tube_t )"
equation "d519 = ( pod_d / 2 - skin_t ) - ( pod_d / 2 - wall_depth + seam_gap )"
equation "d520 = abs(( ( pod_w / 2 - outer_t ) ) + tube_t)"
equation "d521 = abs(pod_d / 2 - wall_depth + seam_gap)"
equation "d522 = ( ( panel_z0 + side_h ) - tube_t ) - ( ( ( panel_z0 + side_h ) - top_h ) + tube_t )"
equation "d524 = ( panel_z0 ) + tube_w"
equation "d526 = ( ( pod_w / 2 - skin_t - bond_t ) ) - ( ( pod_w / 2 - outer_t ) )"
equation "d527 = ( ( pod_d / 2 - wall_depth + seam_gap ) + tube_w ) - ( pod_d / 2 - wall_depth + seam_gap )"
equation "d528 = abs(( pod_w / 2 - outer_t ))"
equation "d529 = abs(pod_d / 2 - wall_depth + seam_gap)"
equation "d530 = ( ( panel_z0 + side_h ) - top_h ) - ( ( panel_z0 ) + tube_w )"
equation "d532 = ( panel_z0 ) + tube_w"
equation "d534 = ( ( ( pod_w / 2 - skin_t - bond_t ) ) - tube_t ) - ( ( ( pod_w / 2 - outer_t ) ) + tube_t )"
equation "d535 = ( ( ( pod_d / 2 - wall_depth + seam_gap ) + tube_w ) - tube_t ) - ( ( pod_d / 2 - wall_depth + seam_gap ) + tube_t )"
equation "d536 = abs(( ( pod_w / 2 - outer_t ) ) + tube_t)"
equation "d537 = abs(( pod_d / 2 - wall_depth + seam_gap ) + tube_t)"
equation "d538 = ( ( panel_z0 + side_h ) - top_h ) - ( ( panel_z0 ) + tube_w )"
equation "d540 = ( panel_z0 ) + tube_w"
equation "d542 = ( ( pod_w / 2 - skin_t - bond_t ) ) - ( ( pod_w / 2 - outer_t ) )"
equation "d543 = ( pod_d / 2 - skin_t ) - ( ( pod_d / 2 - skin_t ) - corner_w )"
equation "d544 = abs(( pod_w / 2 - outer_t ))"
equation "d545 = abs(( pod_d / 2 - skin_t ) - corner_w)"
equation "d546 = ( ( panel_z0 + side_h ) - top_h ) - ( ( panel_z0 ) + tube_w )"
equation "d548 = ( panel_z0 ) + tube_w"
equation "d550 = ( ( ( pod_w / 2 - skin_t - bond_t ) ) - tube_t ) - ( ( ( pod_w / 2 - outer_t ) ) + tube_t )"
equation "d551 = ( ( pod_d / 2 - skin_t ) - tube_t ) - ( ( ( pod_d / 2 - skin_t ) - corner_w ) + tube_t )"
equation "d552 = abs(( ( pod_w / 2 - outer_t ) ) + tube_t)"
equation "d553 = abs(( ( pod_d / 2 - skin_t ) - corner_w ) + tube_t)"
equation "d554 = ( ( panel_z0 + side_h ) - top_h ) - ( ( panel_z0 ) + tube_w )"
equation "d556 = ( panel_z0 ) + tube_w"
equation "d558 = ( ( pod_w / 2 - skin_t - bond_t ) ) - ( ( pod_w / 2 - outer_t ) )"
equation "d559 = ( ( pod_d / 2 - wall_depth + seam_gap ) + stile_pitch + tube_w ) - ( ( pod_d / 2 - wall_depth + seam_gap ) + stile_pitch )"
equation "d560 = abs(( pod_w / 2 - outer_t ))"
equation "d561 = abs(( pod_d / 2 - wall_depth + seam_gap ) + stile_pitch)"
equation "d562 = ( ( panel_z0 + side_h ) - top_h ) - ( ( panel_z0 ) + tube_w )"
equation "d564 = ( panel_z0 ) + tube_w"
equation "d566 = ( ( ( pod_w / 2 - skin_t - bond_t ) ) - stud_t ) - ( ( ( pod_w / 2 - outer_t ) ) + stud_t )"
equation "d567 = ( ( ( pod_d / 2 - wall_depth + seam_gap ) + stile_pitch + tube_w ) - stud_t ) - ( ( ( pod_d / 2 - wall_depth + seam_gap ) + stile_pitch ) + stud_t )"
equation "d568 = abs(( ( pod_w / 2 - outer_t ) ) + stud_t)"
equation "d569 = abs(( ( pod_d / 2 - wall_depth + seam_gap ) + stile_pitch ) + stud_t)"
equation "d570 = ( ( panel_z0 + side_h ) - top_h ) - ( ( panel_z0 ) + tube_w )"
equation "d572 = stile_n_mid"
equation "d574 = stile_pitch"
equation "d576 = panel_z0"
equation "d578 = abs(( pod_w / 2 - skin_t - bond_t - tube_d / 2 ))"
equation "d579 = abs(( pod_d / 2 - wall_depth + seam_gap ) + bolt_edge)"
equation "d580 = tube_t"
equation "d581 = bolt_d"
equation "d583 = ( panel_z0 ) + tube_w"
equation "d585 = abs(( pod_w / 2 - skin_t - bond_t - tube_d / 2 ))"
equation "d586 = abs(( pod_d / 2 - wall_depth + seam_gap ) + bolt_edge)"
equation "d587 = tube_t"
equation "d588 = access_d"
equation "d590 = n_len_bolt"
equation "d592 = len_bolt_pitch"
equation "d594 = panel_z0"
equation "d596 = abs(( pod_w / 2 - skin_t - bond_t - tube_d / 2 ))"
equation "d597 = abs(( pod_d / 2 - wall_depth + seam_gap ) + spigot_edge)"
equation "d598 = tube_t"
equation "d599 = spigot_d"
equation "d601 = panel_z0"
equation "d603 = ( ( ( pod_w / 2 - skin_t - bond_t - tube_d / 2 ) ) + ( spigot_slot - spigot_d ) / 2 ) - ( ( ( pod_w / 2 - skin_t - bond_t - tube_d / 2 ) ) - ( spigot_slot - spigot_d ) / 2 )"
equation "d604 = ( ( ( pod_d / 2 ) - spigot_edge ) + spigot_d / 2 ) - ( ( ( pod_d / 2 ) - spigot_edge ) - spigot_d / 2 )"
equation "d605 = abs(( ( pod_w / 2 - skin_t - bond_t - tube_d / 2 ) ) - ( spigot_slot - spigot_d ) / 2)"
equation "d606 = abs(( ( pod_d / 2 ) - spigot_edge ) - spigot_d / 2)"
equation "d607 = ( ( panel_z0 ) + tube_t ) - ( panel_z0 )"
equation "d609 = panel_z0"
equation "d611 = abs(( ( pod_w / 2 - skin_t - bond_t - tube_d / 2 ) ) - ( spigot_slot - spigot_d ) / 2)"
equation "d612 = abs(( pod_d / 2 ) - spigot_edge)"
equation "d613 = tube_t"
equation "d614 = spigot_d"
equation "d616 = panel_z0"
equation "d618 = abs(( ( pod_w / 2 - skin_t - bond_t - tube_d / 2 ) ) + ( spigot_slot - spigot_d ) / 2)"
equation "d619 = abs(( pod_d / 2 ) - spigot_edge)"
equation "d620 = tube_t"
equation "d621 = spigot_d"
equation "d623 = panel_z0 + side_h"
equation "d625 = abs(( pod_w / 2 - skin_t - bond_t - tube_d / 2 ))"
equation "d626 = abs(( pod_d / 2 - wall_depth + seam_gap ) + bolt_edge)"
equation "d627 = tube_t"
equation "d628 = rivnut_d"
equation "d630 = n_len_bolt"
equation "d632 = len_bolt_pitch"
equation "d634 = panel_z0 + side_h"
equation "d636 = abs(( pod_w / 2 - skin_t - bond_t - tube_d / 2 ))"
equation "d637 = abs(( pod_d / 2 - wall_depth + seam_gap ) + spigot_edge)"
equation "d638 = tube_t"
equation "d639 = rivnut_d"
equation "d641 = panel_z0 + side_h"
equation "d643 = abs(( pod_w / 2 - skin_t - bond_t - tube_d / 2 ))"
equation "d644 = abs(( pod_d / 2 ) - spigot_edge)"
equation "d645 = tube_t"
equation "d646 = rivnut_d"
equation "d648 = pod_d / 2 - wall_depth + seam_gap"
equation "d650 = abs(( pod_w / 2 - skin_t - bond_t - tube_d / 2 ))"
equation "d651 = abs(( panel_z0 ) + bolt_edge)"
equation "d652 = tube_t"
equation "d653 = bolt_d"
equation "d655 = ( pod_d / 2 - wall_depth + seam_gap ) + tube_w"
equation "d657 = abs(( pod_w / 2 - skin_t - bond_t - tube_d / 2 ))"
equation "d658 = abs(( panel_z0 ) + bolt_edge)"
equation "d659 = tube_t"
equation "d660 = access_d"
equation "d662 = n_side_jnt"
equation "d664 = side_jnt_pitch"
equation "d666 = ( pod_w / 2 - outer_t )"
equation "d668 = abs(bolt_line_y)"
equation "d669 = abs(corner_z0 + bolt_edge)"
equation "d670 = tube_t"
equation "d671 = rivnut_d"
equation "d673 = n_side_jnt"
equation "d675 = corner_bolt_pitch"
named bodies: "RAIL - BOTTOM", "RAIL - TOP", "STILE - FRONT", "STILE - BACK", "STILE - MID 1", "STILE - MID 2", "STILE - MID 3"
